Autodesk Fusion 360 part; units mm, degrees
(part 2 of 2)
extrude "Extrude4" cut sketch "Sketch4" against normal blind 5 contours A40 A47 A48 | A40 A45 A46 | A40 A49 A50 | A40 A43 A44 | A40 A42 A51
sketch "Sketch5" plane through (0, 0, 49.5) normal (0, 0, 1) x (-1, 0, 0)
  arc A0 (-29.7865, 18.3783) -> (2.8478, -9.5982) centre (-5.1579, 14.0853) ccw
  arc A1 (-34.9762, -1.2899) -> (2.8478, -9.5982) centre (-14.9898, -0.5528) ccw
  arc A2 (-29.7865, 18.3783) -> (-34.9762, -1.2899) centre (0, 0) ccw
  arc A3 (-9.5814, -33.663) -> (10.0084, -0.2575) centre (-4.1063, -14.427) ccw
  arc A4 (-26.6834, -22.6495) -> (-9.5814, -33.663) centre (0, 0) ccw
  arc A5 (-26.6834, -22.6495) -> (10.0084, -0.2575) centre (-14.9898, -0.5528) ccw
  arc A6 (-12.0351, 32.8657) -> (-8.2484, -5.6745) centre (-5.1579, 14.0853) ccw
  arc A7 (8.2743, 34.0079) -> (-12.0351, 32.8657) centre (0, 0) ccw
  arc A8 (8.2743, 34.0079) -> (-8.2484, -5.6745) centre (11.8021, 9.258) ccw
  arc A9 (29.0546, -19.5149) -> (3.3377, 9.439) centre (12.452, -8.3635) ccw
  arc A10 (13.2953, -32.3765) -> (29.0546, -19.5149) centre (0, 0) ccw
  arc A11 (13.2953, -32.3765) -> (3.3377, 9.439) centre (-4.1063, -14.427) ccw
  arc A12 (27.5381, 21.6021) -> (-7.9456, 6.0912) centre (11.8021, 9.258) ccw
  arc A13 (34.9003, 2.6397) -> (27.5381, 21.6021) centre (0, 0) ccw
  arc A14 (34.9003, 2.6397) -> (-7.9456, 6.0912) centre (12.452, -8.3635) ccw
  arc A15 (-7.6398, -45.468) -> (-6.7845, -45.6035) centre (-7.1731, -45.2889) ccw
  line L0 (-6.7845, -45.6035) -> (-3.2451, -41.2327)
  line L1 (-3.2451, -41.2327) -> (-0.433, -46.1034)
  arc A16 (-0.433, -46.1034) -> (0.433, -46.1034) centre (0, -45.8534) ccw
  line L2 (0.433, -46.1034) -> (3.2451, -41.2327)
  line L3 (3.2451, -41.2327) -> (6.7845, -45.6035)
  arc A17 (6.7845, -45.6035) -> (7.6398, -45.468) centre (7.1731, -45.2889) ccw
  line L4 (7.6398, -45.468) -> (9.6554, -40.2175)
  line L5 (9.6554, -40.2175) -> (13.8349, -43.9807)
  arc A18 (13.8349, -43.9807) -> (14.6586, -43.7131) centre (14.1695, -43.6092) ccw
  line L6 (14.6586, -43.7131) -> (15.8279, -38.2119)
  line L7 (15.8279, -38.2119) -> (20.5447, -41.275)
  arc A19 (20.5447, -41.275) -> (21.3163, -40.8818) centre (20.817, -40.8557) ccw
  line L8 (21.3163, -40.8818) -> (21.6107, -35.2654)
  line L9 (21.6107, -35.2654) -> (26.7486, -37.5529)
  arc A20 (26.7486, -37.5529) -> (27.4492, -37.0439) centre (26.952, -37.0962) ccw
  line L10 (27.4492, -37.0439) -> (26.8613, -31.4506)
  line L11 (26.8613, -31.4506) -> (32.2938, -32.9062)
  arc A21 (32.2938, -32.9062) -> (32.9062, -32.2938) centre (32.4232, -32.4232) ccw
  line L12 (32.9062, -32.2938) -> (31.4506, -26.8613)
  line L13 (31.4506, -26.8613) -> (37.0439, -27.4492)
  arc A22 (37.0439, -27.4492) -> (37.5529, -26.7486) centre (37.0962, -26.952) ccw
  line L14 (37.5529, -26.7486) -> (35.2654, -21.6107)
  line L15 (35.2654, -21.6107) -> (40.8818, -21.3163)
  arc A23 (40.8818, -21.3163) -> (41.275, -20.5447) centre (40.8557, -20.817) ccw
  line L16 (41.275, -20.5447) -> (38.2119, -15.8279)
  line L17 (38.2119, -15.8279) -> (43.7131, -14.6586)
  arc A24 (43.7131, -14.6586) -> (43.9807, -13.8349) centre (43.6092, -14.1695) ccw
  line L18 (43.9807, -13.8349) -> (40.2175, -9.6554)
  line L19 (40.2175, -9.6554) -> (45.468, -7.6398)
  arc A25 (45.468, -7.6398) -> (45.6035, -6.7845) centre (45.2889, -7.1731) ccw
  line L20 (45.6035, -6.7845) -> (41.2327, -3.2451)
  line L21 (41.2327, -3.2451) -> (46.1034, -0.433)
  arc A26 (46.1034, -0.433) -> (46.1034, 0.433) centre (45.8534, 0) ccw
  line L22 (46.1034, 0.433) -> (41.2327, 3.2451)
  line L23 (41.2327, 3.2451) -> (45.6035, 6.7845)
  arc A27 (45.6035, 6.7845) -> (45.468, 7.6398) centre (45.2889, 7.1731) ccw
  line L24 (45.468, 7.6398) -> (40.2175, 9.6554)
  line L25 (40.2175, 9.6554) -> (43.9807, 13.8349)
  arc A28 (43.9807, 13.8349) -> (43.7131, 14.6586) centre (43.6092, 14.1695) ccw
  line L26 (43.7131, 14.6586) -> (38.2119, 15.8279)
  line L27 (38.2119, 15.8279) -> (41.275, 20.5447)
  arc A29 (41.275, 20.5447) -> (40.8818, 21.3163) centre (40.8557, 20.817) ccw
  line L28 (40.8818, 21.3163) -> (35.2654, 21.6107)
  line L29 (35.2654, 21.6107) -> (37.5529, 26.7486)
  arc A30 (37.5529, 26.7486) -> (37.0439, 27.4492) centre (37.0962, 26.952) ccw
  line L30 (37.0439, 27.4492) -> (31.4506, 26.8613)
  line L31 (31.4506, 26.8613) -> (32.9062, 32.2938)
  arc A31 (32.9062, 32.2938) -> (32.2938, 32.9062) centre (32.4232, 32.4232) ccw
  line L32 (32.2938, 32.9062) -> (26.8613, 31.4506)
  line L33 (26.8613, 31.4506) -> (27.4492, 37.0439)
  arc A32 (27.4492, 37.0439) -> (26.7486, 37.5529) centre (26.952, 37.0962) ccw
  line L34 (26.7486, 37.5529) -> (21.6107, 35.2654)
  line L35 (21.6107, 35.2654) -> (21.3163, 40.8818)
  arc A33 (21.3163, 40.8818) -> (20.5447, 41.275) centre (20.817, 40.8557) ccw
  line L36 (20.5447, 41.275) -> (15.8279, 38.2119)
  line L37 (15.8279, 38.2119) -> (14.6586, 43.7131)
  arc A34 (14.6586, 43.7131) -> (13.8349, 43.9807) centre (14.1695, 43.6092) ccw
  line L38 (13.8349, 43.9807) -> (9.6554, 40.2175)
  line L39 (9.6554, 40.2175) -> (7.6398, 45.468)
  arc A35 (7.6398, 45.468) -> (6.7845, 45.6035) centre (7.1731, 45.2889) ccw
  line L40 (6.7845, 45.6035) -> (3.2451, 41.2327)
  line L41 (3.2451, 41.2327) -> (0.433, 46.1034)
  arc A36 (0.433, 46.1034) -> (-0.433, 46.1034) centre (0, 45.8534) ccw
  line L42 (-0.433, 46.1034) -> (-3.2451, 41.2327)
  line L43 (-3.2451, 41.2327) -> (-6.7845, 45.6035)
  arc A37 (-6.7845, 45.6035) -> (-7.6398, 45.468) centre (-7.1731, 45.2889) ccw
  line L44 (-7.6398, 45.468) -> (-9.6554, 40.2175)
  line L45 (-9.6554, 40.2175) -> (-13.8349, 43.9807)
  arc A38 (-13.8349, 43.9807) -> (-14.6586, 43.7131) centre (-14.1695, 43.6092) ccw
  line L46 (-14.6586, 43.7131) -> (-15.8279, 38.2119)
  line L47 (-15.8279, 38.2119) -> (-20.5447, 41.275)
  arc A39 (-20.5447, 41.275) -> (-21.3163, 40.8818) centre (-20.817, 40.8557) ccw
  line L48 (-21.3163, 40.8818) -> (-21.6107, 35.2654)
  line L49 (-21.6107, 35.2654) -> (-26.7486, 37.5529)
  arc A40 (-26.7486, 37.5529) -> (-27.4492, 37.0439) centre (-26.952, 37.0962) ccw
  line L50 (-27.4492, 37.0439) -> (-26.8613, 31.4506)
  line L51 (-26.8613, 31.4506) -> (-32.2938, 32.9062)
  arc A41 (-32.2938, 32.9062) -> (-32.9062, 32.2938) centre (-32.4232, 32.4232) ccw
  line L52 (-32.9062, 32.2938) -> (-31.4506, 26.8613)
  line L53 (-31.4506, 26.8613) -> (-37.0439, 27.4492)
  arc A42 (-37.0439, 27.4492) -> (-37.5529, 26.7486) centre (-37.0962, 26.952) ccw
  line L54 (-37.5529, 26.7486) -> (-35.2654, 21.6107)
  line L55 (-35.2654, 21.6107) -> (-40.8818, 21.3163)
  arc A43 (-40.8818, 21.3163) -> (-41.275, 20.5447) centre (-40.8557, 20.817) ccw
  line L56 (-41.275, 20.5447) -> (-38.2119, 15.8279)
  line L57 (-38.2119, 15.8279) -> (-43.7131, 14.6586)
  arc A44 (-43.7131, 14.6586) -> (-43.9807, 13.8349) centre (-43.6092, 14.1695) ccw
  line L58 (-43.9807, 13.8349) -> (-40.2175, 9.6554)
  line L59 (-40.2175, 9.6554) -> (-45.468, 7.6398)
  arc A45 (-45.468, 7.6398) -> (-45.6035, 6.7845) centre (-45.2889, 7.1731) ccw
  line L60 (-45.6035, 6.7845) -> (-41.2327, 3.2451)
  line L61 (-41.2327, 3.2451) -> (-46.1034, 0.433)
  arc A46 (-46.1034, 0.433) -> (-46.1034, -0.433) centre (-45.8534, 0) ccw
  line L62 (-46.1034, -0.433) -> (-41.2327, -3.2451)
  line L63 (-41.2327, -3.2451) -> (-45.6035, -6.7845)
  arc A47 (-45.6035, -6.7845) -> (-45.468, -7.6398) centre (-45.2889, -7.1731) ccw
  line L64 (-45.468, -7.6398) -> (-40.2175, -9.6554)
  line L65 (-40.2175, -9.6554) -> (-43.9807, -13.8349)
  arc A48 (-43.9807, -13.8349) -> (-43.7131, -14.6586) centre (-43.6092, -14.1695) ccw
  line L66 (-43.7131, -14.6586) -> (-38.2119, -15.8279)
  line L67 (-38.2119, -15.8279) -> (-41.275, -20.5447)
  arc A49 (-41.275, -20.5447) -> (-40.8818, -21.3163) centre (-40.8557, -20.817) ccw
  line L68 (-40.8818, -21.3163) -> (-35.2654, -21.6107)
  line L69 (-35.2654, -21.6107) -> (-37.5529, -26.7486)
  arc A50 (-37.5529, -26.7486) -> (-37.0439, -27.4492) centre (-37.0962, -26.952) ccw
  line L70 (-37.0439, -27.4492) -> (-31.4506, -26.8613)
  line L71 (-31.4506, -26.8613) -> (-32.9062, -32.2938)
  arc A51 (-32.9062, -32.2938) -> (-32.2938, -32.9062) centre (-32.4232, -32.4232) ccw
  line L72 (-32.2938, -32.9062) -> (-26.8613, -31.4506)
  line L73 (-26.8613, -31.4506) -> (-27.4492, -37.0439)
  arc A52 (-27.4492, -37.0439) -> (-26.7486, -37.5529) centre (-26.952, -37.0962) ccw
  line L74 (-26.7486, -37.5529) -> (-21.6107, -35.2654)
  line L75 (-21.6107, -35.2654) -> (-21.3163, -40.8818)
  arc A53 (-21.3163, -40.8818) -> (-20.5447, -41.275) centre (-20.817, -40.8557) ccw
  line L76 (-20.5447, -41.275) -> (-15.8279, -38.2119)
  line L77 (-15.8279, -38.2119) -> (-14.6586, -43.7131)
  arc A54 (-14.6586, -43.7131) -> (-13.8349, -43.9807) centre (-14.1695, -43.6092) ccw
  line L78 (-13.8349, -43.9807) -> (-9.6554, -40.2175)
  line L79 (-9.6554, -40.2175) -> (-7.6398, -45.468)
  circle A55 centre (0, 0) radius 3
  constraint coincident A2.centre A4.centre
extrude "Extrude5" add sketch "Sketch5" along normal blind 10 contours A55
equation "d4 = ( 41 * 2 ) * 1 mm"

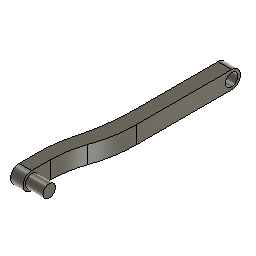
design "connecting rod"
part number: 2026-03-27-15-36-50-826
Autodesk Fusion 360 part; units mm, degrees
sketch "Sketch1" plane through (0, 0, 0) normal (1, 0, 0) x (0, 1, 0)
  circle A0 centre (0, 0) radius 2.5
  dimension "d1" = 5
  constraint coincident A0.centre origin
  measures "d1" diameter of A0
extrude "Extrude1" add sketch "Sketch1" along normal blind 7
sketch "Sketch2" plane through (0, 0, 0) normal (-1, 0, 0) x (0, -1, 0)
  circle A0 centre (0, 0) radius 2.5
  circle A1 centre (0, 0) radius 3.5
  dimension "d4" = 7
  constraint coincident A0.centre A1.centre
  measures "d4" diameter of A1
extrude "Extrude2" add sketch "Sketch2" along normal blind 5 contours A0 | A1
sketch "Sketch3" plane through (-5, 0, 0) normal (-1, 0, 0) x (0, -1, 0)
  circle A0 centre (0, 0) radius 3.5
  circle A1 centre (0, 0) radius 3.5
  line L0 (0, 3.5) -> (-75, 3.5)
  line L1 (-78.5, 0) -> (-78.5, -3.5) construction
  line L2 (-78.5, -3.5) -> (0, -3.5)
  line L3 (0, -3.5) -> (0, 3.5)
  arc A2 (-75, 3.5) -> (-75, -3.5) centre (-75, 0) ccw
  dimension "d7" = 75
  constraint horizontal L0
  constraint vertical L1
  constraint horizontal L2
  constraint vertical L3
  constraint coincident A1 L0.start
  constraint coincident A1 L2.end
  constraint tangent A0 L0
  constraint tangent L0 A2
  constraint tangent L2 A2
  constraint tangent L1 A2
  constraint coincident L1.start A2
  constraint coincident L2 A2.end
  constraint coincident L0 A2.start
  constraint coincident L0.end A2.start
  measures "d7" distance of L0.start L0.end
extrude "Extrude3" add sketch "Sketch3" against normal up to surface (5 mm away) contours A0 A1 L0 L2 A2
sketch "Sketch4" plane through (0, 0, 0) normal (1, 0, 0) x (0, 1, 0)
  line L0 (0, -3.5) -> (75, -3.5)
  arc A0 (75, -3.5) -> (75, 3.5) centre (75, 0) ccw
  line L1 (75, 3.5) -> (0, 3.5)
  arc A1 (0, 3.5) -> (0, -3.5) centre (0, 0) ccw
  circle A2 centre (0, 0) radius 2.5
  circle A3 centre (75, 0) radius 2.5
  dimension "d10" = 5
  constraint concentric A0 A3
  measures "d10" diameter of A3
extrude "Extrude4" add sketch "Sketch4" along normal up to surface (7 mm away) contours A3
extrude "Extrude5" cut 1 faces at (7, 75.3045, -1.0241) along direction (-1, 0, 0) blind 33
sketch "Sketch5" plane through (-5, 0, 0) normal (-1, 0, 0) x (0, -1, 0)
  circle A0 centre (-75, 0) radius 2.5
  arc A1 (0, -3.5) -> (0, 3.5) centre (0, 0) ccw
  line L0 (0, 3.5) -> (-75, 3.5)
  arc A2 (-75, 3.5) -> (-75, -3.5) centre (-75, 0) ccw
  line L1 (-75, -3.5) -> (0, -3.5)
  line L2 (-15, -3.5) -> (-15, 3.5)
  dimension "d15" = 15
  constraint coincident L1 L2.start
  constraint coincident L0 L2.end
  constraint perpendicular L0 L2
  measures "d15" distance of A1.centre L2
extrude "Extrude6" add sketch "Sketch5" against normal blind 10 contours L0 A2 L1 L2
sketch "Sketch6" plane through (5, 0, 0) normal (1, 0, 0) x (0, 1, 0)
  circle A0 centre (75, 0) radius 2.5
  line L0 (15, 3.5) -> (15, -3.5)
  line L1 (15, -3.5) -> (75, -3.5)
  arc A1 (75, -3.5) -> (75, 3.5) centre (75, 0) ccw
  line L2 (75, 3.5) -> (15, 3.5)
extrude "Extrude7" cut sketch "Sketch6" against normal blind 8 from surface at -5.5
fillet "Fillet1" radius 84 1 edges at (-0.5, 15, 0)
fillet "Fillet2" radius 50.5 1 edges at (5, 15, 0)
fillet "Fillet3" radius 48.5 1 edges at (-5, 15, 0)
fillet "Fillet3" radius 38.5 1 edges at (0, 15, 0)

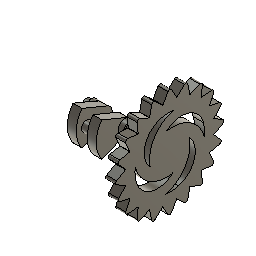
design "shaft"
part number: 2026-03-27-15-48-30-231
Autodesk Fusion 360 part; units mm, degrees
sketch "Sketch1" plane through (0, 0, 0) normal (1, 0, 0) x (0, 1, 0)
  circle A0 centre (0, 0) radius 2.5 construction
  circle A1 centre (0, 0) radius 14.5
  circle A2 centre (0, 0) radius 9.5 construction
  circle A3 centre (-9.4991, -0.128) radius 2.5
  circle A4 centre (0, 0) radius 3.5
  line L0 (1.3394, 3.2336) -> (-11.6607, 8.6184)
  line L1 (1.3394, -3.2336) -> (-11.6607, -8.6184)
  line L2 (0, 0) -> (-7.0024, 0) construction
  dimension "d1" = 29
  dimension "d2" = 5
  dimension "d3" = 5
  dimension "d4" = 5
  dimension "d5" = 7
  dimension "d6" = 45
  dimension "d7" = 22.5
  constraint coincident A0.centre A1.centre
  constraint coincident A2 A3.centre
  constraint concentric A2 A4
  constraint coincident A4 L0.start
  constraint coincident A1 L0.end
  constraint coincident A4 L1.start
  constraint coincident A1 L1.end
  constraint tangent A4 L0
  constraint tangent A4 L1
  constraint coincident A3 L2.end
  constraint horizontal L2
  measures "d1" diameter of A1
  measures "d2" diameter of A0
  measures "d3" distance of A1 A2
  measures "d4" diameter of A3
  measures "d5" diameter of A4
  measures "d6" angle of L0 L1
  measures "d7" angle of L1 L2
extrude "Extrude1" add sketch "Sketch1" along normal blind 4.5 contours A1 A4 L0 L1 | A4 picked at (-7.3196, 4.4977)
sketch "Sketch2" plane through (0, 0, 0) normal (-1, 0, 0) x (0, -1, 0)
  circle A0 centre (9.4991, -0.128) radius 2.5
  line L0 (11.6607, 8.6184) -> (-1.3394, 3.2336)
  arc A1 (-1.3394, 3.2336) -> (-1.3394, -3.2336) centre (0, 0) ccw
  line L1 (-1.3394, -3.2336) -> (11.6607, -8.6184)
  arc A2 (11.6607, -8.6184) -> (11.6607, 8.6184) centre (0, 0) ccw
extrude "Extrude2" add sketch "Sketch2" against normal blind 10 contours A0
sketch "Sketch3" plane through (10, 0, 0) normal (1, 0, 0) x (0, 1, 0)
  circle A0 centre (-9.4991, -0.128) radius 2.5
  line L0 (1.3394, 3.2336) -> (-11.6607, 8.6184)
  circle A1 centre (-9.4991, -0.128) radius 2.5
  line L1 (1.3394, 3.2336) -> (-11.6607, 8.6184)
  arc A2 (-11.6607, 8.6184) -> (-11.6607, -8.6184) centre (0, 0) ccw
  line L2 (-11.6607, -8.6184) -> (1.3394, -3.2336)
  arc A3 (1.3394, -3.2336) -> (1.3394, 3.2336) centre (0, 0) ccw
extrude "Extrude3" add sketch "Sketch3" along normal blind 4.5 contours A0 A1 | L0 L1 A2 L2 A3
sketch "Sketch4" plane through (14.5, 0, 0) normal (1, 0, 0) x (0, 1, 0)
  arc A0 (1.3394, -3.2336) -> (1.3394, 3.2336) centre (0, 0) ccw
  line L0 (1.3394, 3.2336) -> (-11.6607, 8.6184)
  arc A1 (-11.6607, 8.6184) -> (-11.6607, -8.6184) centre (0, 0) ccw
  line L1 (-11.6607, -8.6184) -> (1.3394, -3.2336)
  circle A2 centre (0, 0) radius 3.5
  dimension "d14" = 7
  constraint coincident A0.centre A1.centre
  measures "d14" diameter of A2
extrude "Extrude4" add sketch "Sketch4" along normal blind 2.5 contours A0 A2
sketch "Sketch5" plane through (17, 0, 0) normal (1, 0, 0) x (0, 1, 0)
  circle A0 centre (0, 0) radius 3.5
  circle A1 centre (0, 0) radius 2.5
  dimension "d17" = 5
  constraint concentric A0 A1
  measures "d17" diameter of A1
extrude "Extrude5" add sketch "Sketch5" along normal blind 15 contours A1
sketch "Sketch6" plane through (0, 0, 0) normal (-1, 0, 0) x (0, -1, 0)
  line L0 (11.6607, 8.6184) -> (-1.3394, 3.2336)
  arc A0 (-1.3394, 3.2336) -> (-1.3394, -3.2336) centre (0, 0) ccw
  line L1 (-1.3394, -3.2336) -> (11.6607, -8.6184)
  arc A1 (11.6607, -8.6184) -> (11.6607, 8.6184) centre (0, 0) ccw
  circle A2 centre (0, 0) radius 3.5
  constraint coincident A0.centre A1.centre
extrude "Extrude6" add sketch "Sketch6" along normal blind 2.5 contours A0 A2
sketch "Sketch7" plane through (-2.5, 0, 0) normal (-1, 0, 0) x (0, -1, 0)
  circle A0 centre (0, 0) radius 3.5
  circle A1 centre (0, 0) radius 2.5
  dimension "d22" = 5
  constraint concentric A0 A1
  measures "d22" diameter of A1
extrude "Extrude7" add sketch "Sketch7" along normal blind 2.5 contours A1
sketch "Sketch8" plane through (32, 0, 0) normal (1, 0, 0) x (0, 1, 0)
  circle A0 centre (0, 0) radius 2.5
  circle A1 centre (0, 0) radius 2.5
  circle A2 centre (0, 0) radius 22.5
  dimension "d25" = 20
  dimension "d26" = 5
  constraint concentric A0 A1
  constraint concentric A1 A2
  measures "d25" distance of A1 A2
  measures "d26" diameter of A1
extrude "Extrude8" add sketch "Sketch8" along normal blind 5 contours A0 A1 | A2
sketch "Sketch9" plane through (37, 0, 0) normal (1, 0, 0) x (0, 1, 0)
  circle A0 centre (0, 0) radius 22.5
  line L0 (-3.4641, -22.2317) -> (0, -28.2317)
  line L1 (0, -28.2317) -> (3.4641, -22.2317)
  line L2 (3.4641, -22.2317) -> (-3.4641, -22.2317)
  point P0 (0, -24.2317)
  dimension "d29" = 2
  constraint coincident A0 L1.end
  constraint horizontal L2
  constraint coincident A0 L0.start
  measures "d29" distance of P0 L2
extrude "Extrude9" add sketch "Sketch9" against normal up to surface (5 mm away) contours A0 L0 L1
fillet "Fillet1" radius 1 1 edges at (34.5, 0, -28.2317)
pattern_circular "C-Pattern2" count 20 over 360 about axis through (1.75, 0, 0) along (1, 0, 0) of "Extrude9", "Fillet1"
sketch "Sketch10" plane through (37, 0, 0) normal (1, 0, 0) x (0, 1, 0)
  arc A0 (-9.0842, -25.1558) -> (-7.4369, -25.691) centre (-8.1061, -24.9479) ccw
  line L0 (-7.4369, -25.691) -> (-3.5754, -22.2141)
  arc A1 (-3.5754, -22.2141) -> (-3.4641, -22.2317) centre (0, 0) ccw
  line L1 (-3.4641, -22.2317) -> (-0.866, -26.7317)
  arc A2 (-0.866, -26.7317) -> (0.866, -26.7317) centre (0, -26.2317) ccw
  line L2 (0.866, -26.7317) -> (3.4641, -22.2317)
  arc A3 (3.4641, -22.2317) -> (3.5754, -22.2141) centre (0, 0) ccw
  line L3 (3.5754, -22.2141) -> (7.4369, -25.691)
  arc A4 (7.4369, -25.691) -> (9.0842, -25.1558) centre (8.1061, -24.9479) ccw
  line L4 (9.0842, -25.1558) -> (10.1645, -20.0732)
  arc A5 (10.1645, -20.0732) -> (10.265, -20.022) centre (0, 0) ccw
  line L5 (10.265, -20.022) -> (15.0119, -22.1355)
  arc A6 (15.0119, -22.1355) -> (16.4131, -21.1174) centre (15.4186, -21.2219) ccw
  line L6 (16.4131, -21.1174) -> (15.87, -15.9497)
  arc A7 (15.87, -15.9497) -> (15.9497, -15.87) centre (0, 0) ccw
  line L7 (15.9497, -15.87) -> (21.1174, -16.4131)
  arc A8 (21.1174, -16.4131) -> (22.1355, -15.0119) centre (21.2219, -15.4186) ccw
  line L8 (22.1355, -15.0119) -> (20.022, -10.265)
  arc A9 (20.022, -10.265) -> (20.0732, -10.1645) centre (0, 0) ccw
  line L9 (20.0732, -10.1645) -> (25.1558, -9.0842)
  arc A10 (25.1558, -9.0842) -> (25.691, -7.4369) centre (24.9479, -8.1061) ccw
  line L10 (25.691, -7.4369) -> (22.2141, -3.5754)
  arc A11 (22.2141, -3.5754) -> (22.2317, -3.4641) centre (0, 0) ccw
  line L11 (22.2317, -3.4641) -> (26.7317, -0.866)
  arc A12 (26.7317, -0.866) -> (26.7317, 0.866) centre (26.2317, 0) ccw
  line L12 (26.7317, 0.866) -> (22.2317, 3.4641)
  arc A13 (22.2317, 3.4641) -> (22.2141, 3.5754) centre (0, 0) ccw
  line L13 (22.2141, 3.5754) -> (25.691, 7.4369)
  arc A14 (25.691, 7.4369) -> (25.1558, 9.0842) centre (24.9479, 8.1061) ccw
  line L14 (25.1558, 9.0842) -> (20.0732, 10.1645)
  arc A15 (20.0732, 10.1645) -> (20.022, 10.265) centre (0, 0) ccw
  line L15 (20.022, 10.265) -> (22.1355, 15.0119)
  arc A16 (22.1355, 15.0119) -> (21.1174, 16.4131) centre (21.2219, 15.4186) ccw
  line L16 (21.1174, 16.4131) -> (15.9497, 15.87)
  arc A17 (15.9497, 15.87) -> (15.87, 15.9497) centre (0, 0) ccw
  line L17 (15.87, 15.9497) -> (16.4131, 21.1174)
  arc A18 (16.4131, 21.1174) -> (15.0119, 22.1355) centre (15.4186, 21.2219) ccw
  line L18 (15.0119, 22.1355) -> (10.265, 20.022)
  arc A19 (10.265, 20.022) -> (10.1645, 20.0732) centre (0, 0) ccw
  line L19 (10.1645, 20.0732) -> (9.0842, 25.1558)
  arc A20 (9.0842, 25.1558) -> (7.4369, 25.691) centre (8.1061, 24.9479) ccw
  line L20 (7.4369, 25.691) -> (3.5754, 22.2141)
  arc A21 (3.5754, 22.2141) -> (3.4641, 22.2317) centre (0, 0) ccw
  line L21 (3.4641, 22.2317) -> (0.866, 26.7317)
  arc A22 (0.866, 26.7317) -> (-0.866, 26.7317) centre (0, 26.2317) ccw
  line L22 (-0.866, 26.7317) -> (-3.4641, 22.2317)
  arc A23 (-3.4641, 22.2317) -> (-3.5754, 22.2141) centre (0, 0) ccw
  line L23 (-3.5754, 22.2141) -> (-7.4369, 25.691)
  arc A24 (-7.4369, 25.691) -> (-9.0842, 25.1558) centre (-8.1061, 24.9479) ccw
  line L24 (-9.0842, 25.1558) -> (-10.1645, 20.0732)
  arc A25 (-10.1645, 20.0732) -> (-10.265, 20.022) centre (0, 0) ccw
  line L25 (-10.265, 20.022) -> (-15.0119, 22.1355)
  arc A26 (-15.0119, 22.1355) -> (-16.4131, 21.1174) centre (-15.4186, 21.2219) ccw
  line L26 (-16.4131, 21.1174) -> (-15.87, 15.9497)
  arc A27 (-15.87, 15.9497) -> (-15.9497, 15.87) centre (0, 0) ccw
  line L27 (-15.9497, 15.87) -> (-21.1174, 16.4131)
  arc A28 (-21.1174, 16.4131) -> (-22.1355, 15.0119) centre (-21.2219, 15.4186) ccw
  line L28 (-22.1355, 15.0119) -> (-20.022, 10.265)
  arc A29 (-20.022, 10.265) -> (-20.0732, 10.1645) centre (0, 0) ccw
  line L29 (-20.0732, 10.1645) -> (-25.1558, 9.0842)
  arc A30 (-25.1558, 9.0842) -> (-25.691, 7.4369) centre (-24.9479, 8.1061) ccw
  line L30 (-25.691, 7.4369) -> (-22.2141, 3.5754)
  arc A31 (-22.2141, 3.5754) -> (-22.2317, 3.4641) centre (0, 0) ccw
  line L31 (-22.2317, 3.4641) -> (-26.7317, 0.866)
  arc A32 (-26.7317, 0.866) -> (-26.7317, -0.866) centre (-26.2317, 0) ccw
  line L32 (-26.7317, -0.866) -> (-22.2317, -3.4641)
  arc A33 (-22.2317, -3.4641) -> (-22.2141, -3.5754) centre (0, 0) ccw
  line L33 (-22.2141, -3.5754) -> (-25.691, -7.4369)
  arc A34 (-25.691, -7.4369) -> (-25.1558, -9.0842) centre (-24.9479, -8.1061) ccw
  line L34 (-25.1558, -9.0842) -> (-20.0732, -10.1645)
  arc A35 (-20.0732, -10.1645) -> (-20.022, -10.265) centre (0, 0) ccw
  line L35 (-20.022, -10.265) -> (-22.1355, -15.0119)
  arc A36 (-22.1355, -15.0119) -> (-21.1174, -16.4131) centre (-21.2219, -15.4186) ccw
  line L36 (-21.1174, -16.4131) -> (-15.9497, -15.87)
  arc A37 (-15.9497, -15.87) -> (-15.87, -15.9497) centre (0, 0) ccw
  line L37 (-15.87, -15.9497) -> (-16.4131, -21.1174)
  arc A38 (-16.4131, -21.1174) -> (-15.0119, -22.1355) centre (-15.4186, -21.2219) ccw
  line L38 (-15.0119, -22.1355) -> (-10.265, -20.022)
  arc A39 (-10.265, -20.022) -> (-10.1645, -20.0732) centre (0, 0) ccw
  line L39 (-10.1645, -20.0732) -> (-9.0842, -25.1558)
  circle A40 centre (0, 0) radius 5
  circle A41 centre (0, 0) radius 17.5
  arc A42 (16.9354, 4.4092) -> (-4.8387, -1.2598) centre (6.0484, 1.5747) ccw
  arc A43 (2.1966, 17.3616) -> (-9.6774, -2.5195) centre (6.0484, 1.5747) ccw
  arc A44 (-4.4092, 16.9354) -> (1.2598, -4.8387) centre (-1.5747, 6.0484) ccw
  arc A45 (-17.3616, 2.1966) -> (2.5195, -9.6774) centre (-1.5747, 6.0484) ccw
  arc A46 (-16.9354, -4.4092) -> (4.8387, 1.2598) centre (-6.0484, -1.5747) ccw
  arc A47 (-2.1966, -17.3616) -> (9.6774, 2.5195) centre (-6.0484, -1.5747) ccw
  arc A48 (4.4092, -16.9354) -> (-1.2598, 4.8387) centre (1.5747, -6.0484) ccw
  arc A49 (17.3616, -2.1966) -> (-2.5195, 9.6774) centre (1.5747, -6.0484) ccw
  dimension "d38" = 35
  dimension "d39" = 10
  dimension "d42" = 360
  constraint concentric A1 A40
  constraint concentric A40 A41
  constraint tangent A41 A42
  constraint tangent A40 A42
  constraint coincident A40 A42.end
  constraint coincident A41 A42.start
  constraint concentric A42 A43
  constraint coincident A41 A43.start
  measures "d38" diameter of A41
  measures "d39" diameter of A40
extrude "Extrude10" cut sketch "Sketch10" against normal blind 8 contours A41 A45 A46 | A41 A43 A44 | A41 A47 A48 | A41 A42 A49

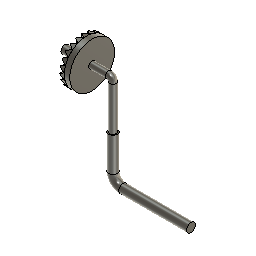
design "rotary gear"
part number: 2026-03-28-01-42-28-752
Autodesk Fusion 360 part; units mm, degrees
sketch "Sketch1" plane through (0, 0, 0) normal (1, 0, 0) x (0, 1, 0)
  circle A0 centre (0, 0) radius 3
  dimension "d1" = 6
  constraint coincident A0.centre origin
  measures "d1" diameter of A0
extrude "Extrude1" add sketch "Sketch1" along normal blind 16
sketch "Sketch2" plane through (16, 0, 0) normal (1, 0, 0) x (0, 1, 0)
  circle A0 centre (0, 0) radius 3
  circle A1 centre (0, 0) radius 16.5
  dimension "d4" = 33
  constraint coincident A0.centre A1.centre
  measures "d4" diameter of A1
extrude "Extrude2" add sketch "Sketch2" along normal blind 4 contours A0 | A1
sketch "Sketch3" plane through (0, 0, 0) normal (0, 0, 1) x (1, 0, 0)
  line L0 (16, -2.3221) -> (16, 2.2967)
  line L1 (16, 2.2967) -> (12, -0.0127)
  line L2 (12, -0.0127) -> (16, -2.3221)
  line L3 (16, -16.5) -> (16, 16.5)
  point P0 (14.6667, -0.0127)
  dimension "d7" = 4
  constraint vertical L0
  constraint coincident L0.start L3
  measures "d7" horizontal distance of L0.start L1.end
extrude "Extrude3" add sketch "Sketch3" along normal blind 4 from surface at 12.5
fillet "Fillet2" radius 0.5 1 edges at (12, -0.0127, 14.5)
pattern_circular "C-Pattern2" count 23 over 360 about axis through (1.75, 0, 0) along (1, 0, 0) of "Extrude3", "Fillet2"
sketch "Sketch4" plane through (20, 0, 0) normal (1, 0, 0) x (0, 1, 0)
  circle A0 centre (0, 0) radius 2.5
  circle A1 centre (0, 0) radius 16.5
  dimension "d19" = 5
  constraint coincident A0.centre A1.centre
  measures "d19" diameter of A0
extrude "Extrude4" add sketch "Sketch4" along normal blind 5 contours A0
extrude "Extrude5" add 1 faces at (25, -0.8863, 0.2321) along direction (1, 0, 0) blind 5
ref_plane "WorkPlane1" through (27.1761, 0, -2.5) normal (0, 0, -1) x (0, -1, 0)
sketch "Sketch6" plane through (30, 0, 0) normal (1, 0, 0) x (0, 1, 0)
  circle A0 centre (0, 0) radius 2.5
sketch "Sketch7" plane through (0, 0, 0) normal (0, 1, 0) x (1, 0, 0)
  line L0 (30, 0) -> (32.3663, 0)
  arc A0 (32.3663, 0) -> (35.3663, 3) centre (32.3663, 3) ccw
  line L1 (35.3663, 3) -> (35.3663, 5)
  point P0 (30, 0)
  dimension "d28" = 3
  dimension "d29" = 2
  constraint horizontal L0
  constraint tangent L0 A0
  constraint coincident P0 L0.start
  constraint tangent A0 L1
  constraint vertical L1
  measures "d28" radius of A0
  measures "d29" distance of A0.end L1.end
sweep "Sweep1" add profiles "Sketch6" path "Sketch7" along L0 A0 L1 section 1
extrude "Extrude6" add 1 faces at (36.1973, 0.9769, -5) along direction (0, 0, -1) blind 50
sketch "Sketch8" plane through (0, 0, -55) normal (0, 0, -1) x (1, 0, 0)
  circle A0 centre (35.3663, 0) radius 2.5
  circle A1 centre (35.3663, 0) radius 3.25
  dimension "d38" = 6.5
  constraint concentric A0 A1
  measures "d38" diameter of A1
extrude "Extrude7" add sketch "Sketch8" against normal blind 20
sketch "Sketch9" plane through (0, 0, -55) normal (0, 0, -1) x (1, 0, 0)
  circle A0 centre (35.3663, 0) radius 3.25
sketch "Sketch10" plane through (0, 0, 0) normal (0, 1, 0) x (1, 0, 0)
  line L0 (35.3663, 55) -> (35.3663, 60)
  arc A0 (42.8663, 67.5) -> (35.3663, 60) centre (42.8663, 60) ccw
  line L1 (42.8663, 67.5) -> (92.8663, 67.5)
  point P0 (35.3663, 55)
  dimension "d43" = 15
  dimension "d44" = 50
  dimension "d45" = 5
  constraint vertical L0
  constraint tangent L0 A0
  constraint coincident P0 L0.start
  constraint tangent A0 L1
  measures "d43" diameter of A0
  measures "d44" distance of A0.start L1.end
  measures "d45" distance of P0 L0.end
sketch "Sketch11" plane through (0, 0, -55) normal (0, 0, -1) x (1, 0, 0)
  circle A0 centre (35.3663, 0) radius 3.25
sweep "Sweep2" add profiles "Sketch9" path "Sketch10" along L1 A0 L0 section 1
